Autodesk Fusion 360 part; units mm, degrees
(part 2 of 3)
sketch "Controller support outside regulator reserve (2)" plane through (0, 0, -13) normal (0, 0, 1) x (1, 0, 0) in component "CORE | ElectronicsCassette"
  line L0 (24.2, -4.8) -> (25.8, -4.8)
  line L1 (25.8, -4.8) -> (25.8, -3.2)
  line L2 (25.8, -3.2) -> (24.2, -3.2)
  line L3 (24.2, -3.2) -> (24.2, -4.8)
extrude "Controller support outside regulator reserve (3)" add sketch "Controller support outside regulator reserve (2)" along normal blind 13 bodies 3 in component "CORE | ElectronicsCassette"
ref_plane "WorkPlane17" through (0, 0, -13) normal (0, 0, 1) x (1, 0, 0) in component "CORE | ElectronicsCassette"
sketch "Controller support outside regulator reserve (3)" plane through (0, 0, -13) normal (0, 0, 1) x (1, 0, 0) in component "CORE | ElectronicsCassette"
  line L0 (24.2, 3.2) -> (25.8, 3.2)
  line L1 (25.8, 3.2) -> (25.8, 4.8)
  line L2 (25.8, 4.8) -> (24.2, 4.8)
  line L3 (24.2, 4.8) -> (24.2, 3.2)
extrude "Controller support outside regulator reserve (4)" add sketch "Controller support outside regulator reserve (3)" along normal blind 13 bodies 3 in component "CORE | ElectronicsCassette"
ref_plane "WorkPlane18" through (0, 0, -15) normal (0, 0, 1) x (1, 0, 0) in component "CORE | ElectronicsCassette"
sketch "Reserved harness route at carrier edge" plane through (0, 0, -15) normal (0, 0, 1) x (1, 0, 0) in component "CORE | ElectronicsCassette"
  line L0 (-7, -23.8) -> (7, -23.8)
  arc A0 (7, -26.2) -> (7, -23.8) centre (7, -25) ccw
  line L1 (7, -26.2) -> (-7, -26.2)
  arc A1 (-7, -23.8) -> (-7, -26.2) centre (-7, -25) ccw
  line L2 (-7, 26.2) -> (7, 26.2)
  arc A2 (7, 23.8) -> (7, 26.2) centre (7, 25) ccw
  line L3 (7, 23.8) -> (-7, 23.8)
  arc A3 (-7, 26.2) -> (-7, 23.8) centre (-7, 25) ccw
extrude "Reserved harness route at carrier edge (1)" cut sketch "Reserved harness route at carrier edge" along normal blind 2 bodies 3 in component "CORE | ElectronicsCassette"
ref_plane "WorkPlane1" through (0, 0, 4) normal (0, 0, 1) x (1, 0, 0) in component "LEG | Centred proximal clevis"
sketch "Closed yaw cap" plane through (0, 0, 4) normal (0, 0, 1) x (1, 0, 0) in component "LEG | Centred proximal clevis"
  circle A0 centre (0, 0) radius 16
extrude "Closed yaw cap (1)" add sketch "Closed yaw cap" along normal blind 4.8 separate body makes body 4 in component "LEG | Centred proximal clevis"
ref_plane "WorkPlane2" through (0, 0, 4) normal (0, 0, 1) x (1, 0, 0) in component "LEG | Centred proximal clevis"
sketch "Symmetric short proximal link" plane through (0, 0, 4) normal (0, 0, 1) x (1, 0, 0) in component "LEG | Centred proximal clevis"
  line L0 (0, -16) -> (16, -14)
  line L1 (16, -14) -> (34, -20.8)
  line L2 (34, -20.8) -> (34, 20.8)
  line L3 (34, 20.8) -> (16, 14)
  line L4 (16, 14) -> (0, 16)
  line L5 (0, 16) -> (0, -16)
extrude "Symmetric short proximal link (1)" add sketch "Symmetric short proximal link" along normal blind 2.4 bodies 4 in component "LEG | Centred proximal clevis"
ref_plane "WorkPlane3" through (0, 0, 4) normal (0, 0, 1) x (1, 0, 0) in component "LEG | Centred proximal clevis"
sketch "Yaw output coupling reserve" plane through (0, 0, 4) normal (0, 0, 1) x (1, 0, 0) in component "LEG | Centred proximal clevis"
  circle A0 centre (0, 0) radius 13.8
extrude "Yaw output coupling reserve (1)" cut sketch "Yaw output coupling reserve" along normal blind 3.2 bodies 4 in component "LEG | Centred proximal clevis"
ref_plane "WorkPlane4" through (0, -16.1, 0) normal (0, 1, 0) x (0, 0, 1) in component "LEG | Centred proximal clevis"
sketch "Bilateral internal shoulder support" plane through (0, -16.1, 0) normal (0, 1, 0) x (1, 0, 0) in component "LEG | Centred proximal clevis"
  line L0 (38.0299, -7.6076) -> (49.0299, 9.3924)
  arc A0 (49.0299, 9.3924) -> (40.9701, 14.6076) centre (45, 12) ccw
  line L1 (40.9701, 14.6076) -> (29.9701, -2.3924)
  arc A1 (29.9701, -2.3924) -> (38.0299, -7.6076) centre (34, -5) ccw
extrude "Bilateral internal shoulder support (1)" add sketch "Bilateral internal shoulder support" along normal blind 1.8 bodies 4 in component "LEG | Centred proximal clevis"
ref_plane "WorkPlane5" through (0, -16.1, 0) normal (0, 1, 0) x (0, 0, 1) in component "LEG | Centred proximal clevis"
sketch "Shoulder pivot plate inside upper enclosure" plane through (0, -16.1, 0) normal (0, 1, 0) x (1, 0, 0) in component "LEG | Centred proximal clevis"
  circle A0 centre (45, 12) radius 11.2
extrude "Shoulder pivot plate inside upper enclosure (1)" add sketch "Shoulder pivot plate inside upper enclosure" along normal blind 1.8 bodies 4 in component "LEG | Centred proximal clevis"
ref_plane "WorkPlane6" through (0, -16.1, 0) normal (0, 1, 0) x (0, 0, 1) in component "LEG | Centred proximal clevis"
sketch "Provisional axis/tool access hidden by red upper cover" plane through (0, -16.1, 0) normal (0, 1, 0) x (1, 0, 0) in component "LEG | Centred proximal clevis"
  circle A0 centre (45, 12) radius 3.2
extrude "Provisional axis/tool access hidden by red upper cover (1)" cut sketch "Provisional axis/tool access hidden by red upper cover" along normal blind 1.8 bodies 4 in component "LEG | Centred proximal clevis"
ref_plane "WorkPlane7" through (0, 14.3, 0) normal (0, 1, 0) x (0, 0, 1) in component "LEG | Centred proximal clevis"
sketch "Bilateral internal shoulder support (1)" plane through (0, 14.3, 0) normal (0, 1, 0) x (1, 0, 0) in component "LEG | Centred proximal clevis"
  line L0 (38.0299, -7.6076) -> (49.0299, 9.3924)
  arc A0 (49.0299, 9.3924) -> (40.9701, 14.6076) centre (45, 12) ccw
  line L1 (40.9701, 14.6076) -> (29.9701, -2.3924)
  arc A1 (29.9701, -2.3924) -> (38.0299, -7.6076) centre (34, -5) ccw
extrude "Bilateral internal shoulder support (2)" add sketch "Bilateral internal shoulder support (1)" along normal blind 1.8 bodies 4 in component "LEG | Centred proximal clevis"
ref_plane "WorkPlane8" through (0, 14.3, 0) normal (0, 1, 0) x (0, 0, 1) in component "LEG | Centred proximal clevis"
sketch "Shoulder pivot plate inside upper enclosure (1)" plane through (0, 14.3, 0) normal (0, 1, 0) x (1, 0, 0) in component "LEG | Centred proximal clevis"
  circle A0 centre (45, 12) radius 11.2
extrude "Shoulder pivot plate inside upper enclosure (2)" add sketch "Shoulder pivot plate inside upper enclosure (1)" along normal blind 1.8 bodies 4 in component "LEG | Centred proximal clevis"
ref_plane "WorkPlane9" through (0, 14.3, 0) normal (0, 1, 0) x (0, 0, 1) in component "LEG | Centred proximal clevis"
sketch "Provisional axis/tool access hidden by red upper cover (1)" plane through (0, 14.3, 0) normal (0, 1, 0) x (1, 0, 0) in component "LEG | Centred proximal clevis"
  circle A0 centre (45, 12) radius 3.2
extrude "Provisional axis/tool access hidden by red upper cover (2)" cut sketch "Provisional axis/tool access hidden by red upper cover (1)" along normal blind 1.8 bodies 4 in component "LEG | Centred proximal clevis"
ref_plane "WorkPlane1" through (0, -18.7, 0) normal (0, 1, 0) x (0, 0, 1) in component "LEG | Continuous centred upper enclosure"
sketch "One continuous upper arm outer skin" plane through (0, -18.7, 0) normal (0, 1, 0) x (1, 0, 0) in component "LEG | Continuous centred upper enclosure"
  line L0 (0, -14) -> (52, -14)
  arc A0 (52, -14) -> (52, 14) centre (52, 0) ccw
  line L1 (52, 14) -> (0, 14)
  arc A1 (0, 14) -> (0, -14) centre (0, 0) ccw
extrude "One continuous upper arm outer skin (1)" add sketch "One continuous upper arm outer skin" along normal blind 35.3 separate body makes body 5 in component "LEG | Continuous centred upper enclosure"
ref_plane "WorkPlane2" through (0, -16.9, 0) normal (0, 1, 0) x (0, 0, 1) in component "LEG | Continuous centred upper enclosure"
sketch "Two-actuator interior open at front service cover" plane through (0, -16.9, 0) normal (0, 1, 0) x (1, 0, 0) in component "LEG | Continuous centred upper enclosure"
  line L0 (0, -12.2) -> (52, -12.2)
  arc A0 (52, -12.2) -> (52, 12.2) centre (52, 0) ccw
  line L1 (52, 12.2) -> (0, 12.2)
  arc A1 (0, 12.2) -> (0, -12.2) centre (0, 0) ccw
extrude "Two-actuator interior open at front service cover (1)" cut sketch "Two-actuator interior open at front service cover" along normal blind 33.5 bodies 5 in component "LEG | Continuous centred upper enclosure"
ref_plane "WorkPlane3" through (0, -16.5, 0) normal (0, 1, 0) x (0, 0, 1) in component "LEG | Continuous centred upper enclosure"
sketch "Narrow fixed shoulder clevis entry slot" plane through (0, -16.5, 0) normal (0, 1, 0) x (1, 0, 0) in component "LEG | Continuous centred upper enclosure"
  line L0 (-6, -9) -> (22, -9)
  line L1 (22, -9) -> (22, -26)
  line L2 (22, -26) -> (-6, -26)
  line L3 (-6, -26) -> (-6, -9)
extrude "Narrow fixed shoulder clevis entry slot (1)" cut sketch "Narrow fixed shoulder clevis entry slot" along normal blind 2.5 bodies 5 in component "LEG | Continuous centred upper enclosure"
ref_plane "WorkPlane4" through (0, -16.5, 0) normal (0, 1, 0) x (0, 0, 1) in component "LEG | Continuous centred upper enclosure"
sketch "Narrow lower clevis swept exit slot" plane through (0, -16.5, 0) normal (0, 1, 0) x (1, 0, 0) in component "LEG | Continuous centred upper enclosure"
  line L0 (18, 30) -> (66, 30)
  line L1 (66, 30) -> (66, 7)
  line L2 (66, 7) -> (18, 7)
  line L3 (18, 7) -> (18, 30)
extrude "Narrow lower clevis swept exit slot (1)" cut sketch "Narrow lower clevis swept exit slot" along normal blind 2.5 bodies 5 in component "LEG | Continuous centred upper enclosure"
ref_plane "WorkPlane5" through (0, 14, 0) normal (0, 1, 0) x (0, 0, 1) in component "LEG | Continuous centred upper enclosure"
sketch "Narrow fixed shoulder clevis entry slot (1)" plane through (0, 14, 0) normal (0, 1, 0) x (1, 0, 0) in component "LEG | Continuous centred upper enclosure"
  line L0 (-6, -9) -> (22, -9)
  line L1 (22, -9) -> (22, -26)
  line L2 (22, -26) -> (-6, -26)
  line L3 (-6, -26) -> (-6, -9)
extrude "Narrow fixed shoulder clevis entry slot (2)" cut sketch "Narrow fixed shoulder clevis entry slot (1)" along normal blind 2.5 bodies 5 in component "LEG | Continuous centred upper enclosure"
ref_plane "WorkPlane6" through (0, 14, 0) normal (0, 1, 0) x (0, 0, 1) in component "LEG | Continuous centred upper enclosure"
sketch "Narrow lower clevis swept exit slot (1)" plane through (0, 14, 0) normal (0, 1, 0) x (1, 0, 0) in component "LEG | Continuous centred upper enclosure"
  line L0 (18, 30) -> (66, 30)
  line L1 (66, 30) -> (66, 7)
  line L2 (66, 7) -> (18, 7)
  line L3 (18, 7) -> (18, 30)
extrude "Narrow lower clevis swept exit slot (2)" cut sketch "Narrow lower clevis swept exit slot (1)" along normal blind 2.5 bodies 5 in component "LEG | Continuous centred upper enclosure"
ref_plane "WorkPlane7" through (0, 0, 4) normal (0, 0, 1) x (1, 0, 0) in component "LEG | Continuous centred upper enclosure"
sketch "Upper central retention bridge in actuator gap" plane through (0, 0, 4) normal (0, 0, 1) x (1, 0, 0) in component "LEG | Continuous centred upper enclosure"
  line L0 (22.2, -17.4) -> (29.8, -17.4)
  line L1 (29.8, -17.4) -> (29.8, 16.6)
  line L2 (29.8, 16.6) -> (22.2, 16.6)
  line L3 (22.2, 16.6) -> (22.2, -17.4)
extrude "Upper central retention bridge in actuator gap (1)" add sketch "Upper central retention bridge in actuator gap" along normal blind 8 bodies 5 in component "LEG | Continuous centred upper enclosure"
ref_plane "WorkPlane8" through (0, 0, 4.7) normal (0, 0, 1) x (1, 0, 0) in component "LEG | Continuous centred upper enclosure"
sketch "Keyed cover tongue pocket" plane through (0, 0, 4.7) normal (0, 0, 1) x (1, 0, 0) in component "LEG | Continuous centred upper enclosure"
  line L0 (22.4, 10) -> (29.6, 10)
  line L1 (29.6, 10) -> (29.6, 16.6)
  line L2 (29.6, 16.6) -> (22.4, 16.6)
  line L3 (22.4, 16.6) -> (22.4, 10)
extrude "Keyed cover tongue pocket (1)" cut sketch "Keyed cover tongue pocket" along normal blind 6.8 bodies 5 in component "LEG | Continuous centred upper enclosure"
ref_plane "WorkPlane9" through (0, -18.7, 0) normal (0, 1, 0) x (0, 0, 1) in component "LEG | Continuous centred upper enclosure"
sketch "Single central rear service screw path" plane through (0, -18.7, 0) normal (0, 1, 0) x (1, 0, 0) in component "LEG | Continuous centred upper enclosure"
  circle A0 centre (26, -8.1) radius 1.7
extrude "Single central rear service screw path (1)" cut sketch "Single central rear service screw path" along normal blind 28.9 bodies 5 in component "LEG | Continuous centred upper enclosure"
ref_plane "WorkPlane10" through (0, -18.7, 0) normal (0, 1, 0) x (0, 0, 1) in component "LEG | Continuous centred upper enclosure"
sketch "Flush rear screw head recess" plane through (0, -18.7, 0) normal (0, 1, 0) x (1, 0, 0) in component "LEG | Continuous centred upper enclosure"
  circle A0 centre (26, -8.1) radius 3.1
extrude "Flush rear screw head recess (1)" cut sketch "Flush rear screw head recess" along normal blind 1.8 bodies 5 in component "LEG | Continuous centred upper enclosure"
ref_plane "WorkPlane1" through (0, 16.9, 0) normal (0, 1, 0) x (0, 0, 1) in component "LEG | Full red front service panel"
sketch "Closed front panel hides both actuator bodies" plane through (0, 16.9, 0) normal (0, 1, 0) x (1, 0, 0) in component "LEG | Full red front service panel"
  line L0 (0, -14) -> (52, -14)
  arc A0 (52, -14) -> (52, 14) centre (52, 0) ccw
  line L1 (52, 14) -> (0, 14)
  arc A1 (0, 14) -> (0, -14) centre (0, 0) ccw
extrude "Closed front panel hides both actuator bodies (1)" add sketch "Closed front panel hides both actuator bodies" along normal blind 1.8 separate body makes body 6 in component "LEG | Full red front service panel"
ref_plane "WorkPlane2" through (0, 0, 5) normal (0, 0, 1) x (1, 0, 0) in component "LEG | Full red front service panel"
sketch "Single keyed internal retention tongue" plane through (0, 0, 5) normal (0, 0, 1) x (1, 0, 0) in component "LEG | Full red front service panel"
  line L0 (22.8, 10.2) -> (29.2, 10.2)
  line L1 (29.2, 10.2) -> (29.2, 17)
  line L2 (29.2, 17) -> (22.8, 17)
  line L3 (22.8, 17) -> (22.8, 10.2)
extrude "Single keyed internal retention tongue (1)" add sketch "Single keyed internal retention tongue" along normal blind 6.2 bodies 6 in component "LEG | Full red front service panel"
ref_plane "WorkPlane3" through (0, 10.2, 0) normal (0, 1, 0) x (0, 0, 1) in component "LEG | Full red front service panel"
sketch "Provisional M3 insert cavity" plane through (0, 10.2, 0) normal (0, 1, 0) x (1, 0, 0) in component "LEG | Full red front service panel"
  circle A0 centre (26, -8.1) radius 2.1
extrude "Provisional M3 insert cavity (1)" cut sketch "Provisional M3 insert cavity" along normal blind 4.2 bodies 6 in component "LEG | Full red front service panel"
ref_plane "WorkPlane1" through (0, 14.3, 0) normal (0, 1, 0) x (0, 0, 1) in component "LEG | Centred tapered lower arm"
sketch "Internal forward knee pivot plate" plane through (0, 14.3, 0) normal (0, 1, 0) x (1, 0, 0) in component "LEG | Centred tapered lower arm"
  circle A0 centre (0, 0) radius 11.2
extrude "Internal forward knee pivot plate (1)" add sketch "Internal forward knee pivot plate" along normal blind 1.8 separate body makes body 7 in component "LEG | Centred tapered lower arm"
ref_plane "WorkPlane2" through (0, 14.3, 0) normal (0, 1, 0) x (0, 0, 1) in component "LEG | Centred tapered lower arm"
sketch "Forward inner fork leg" plane through (0, 14.3, 0) normal (0, 1, 0) x (1, 0, 0) in component "LEG | Centred tapered lower arm"
  line L0 (0, 10) -> (14, 9)
  line L1 (14, 9) -> (28, 7.5)
  line L2 (28, 7.5) -> (40, 6.5)
  line L3 (40, 6.5) -> (40, -6.5)
  line L4 (40, -6.5) -> (28, -7.5)
  line L5 (28, -7.5) -> (14, -9)
  line L6 (14, -9) -> (0, -10)
  line L7 (0, -10) -> (0, 10)
extrude "Forward inner fork leg (1)" add sketch "Forward inner fork leg" along normal blind 1.8 bodies 7 in component "LEG | Centred tapered lower arm"
ref_plane "WorkPlane3" through (38, 0, 0) normal (1, 0, 0) x (0, 1, 0) in component "LEG | Centred tapered lower arm"
sketch "Symmetric transition into centred lower beam section" plane through (38, 0, 0) normal (1, 0, 0) x (0, 0, -1) in component "LEG | Centred tapered lower arm"
  line L0 (6.5, -14.9) -> (6.5, 14.9)
  arc A0 (6.5, 14.9) -> (5.3, 16.1) centre (5.3, 14.9) ccw
  line L1 (5.3, 16.1) -> (-5.3, 16.1)
  arc A1 (-5.3, 16.1) -> (-6.5, 14.9) centre (-5.3, 14.9) ccw
  line L2 (-6.5, 14.9) -> (-6.5, -14.9)
  arc A2 (-6.5, -14.9) -> (-5.3, -16.1) centre (-5.3, -14.9) ccw
  line L3 (-5.3, -16.1) -> (5.3, -16.1)
  arc A3 (5.3, -16.1) -> (6.5, -14.9) centre (5.3, -14.9) ccw
ref_plane "WorkPlane4" through (48, 0, 0) normal (1, 0, 0) x (0, 1, 0) in component "LEG | Centred tapered lower arm"
sketch "Symmetric transition into centred lower beam section (1)" plane through (48, 0, 0) normal (1, 0, 0) x (0, 0, -1) in component "LEG | Centred tapered lower arm"
  line L0 (5.5, -2.8) -> (5.5, 2.8)
  arc A0 (5.5, 2.8) -> (4.3, 4) centre (4.3, 2.8) ccw
  line L1 (4.3, 4) -> (-4.3, 4)
  arc A1 (-4.3, 4) -> (-5.5, 2.8) centre (-4.3, 2.8) ccw
  line L2 (-5.5, 2.8) -> (-5.5, -2.8)
  arc A2 (-5.5, -2.8) -> (-4.3, -4) centre (-4.3, -2.8) ccw
  line L3 (-4.3, -4) -> (4.3, -4)
  arc A3 (4.3, -4) -> (5.5, -2.8) centre (4.3, -2.8) ccw
loft "Symmetric transition into centred lower beam" add profiles "Symmetric transition into centred lower beam section", "Symmetric transition into centred lower beam section (1)" section 1 section 2 bodies 7 in component "LEG | Centred tapered lower arm"
ref_plane "WorkPlane5" through (0, -16.1, 0) normal (0, 1, 0) x (0, 0, 1) in component "LEG | Centred tapered lower arm"
sketch "Rear inner fork leg linked by transition" plane through (0, -16.1, 0) normal (0, 1, 0) x (1, 0, 0) in component "LEG | Centred tapered lower arm"
  line L0 (0, 10) -> (14, 9)
  line L1 (14, 9) -> (28, 7.5)
  line L2 (28, 7.5) -> (40, 6.5)
  line L3 (40, 6.5) -> (40, -6.5)
  line L4 (40, -6.5) -> (28, -7.5)
  line L5 (28, -7.5) -> (14, -9)
  line L6 (14, -9) -> (0, -10)
  line L7 (0, -10) -> (0, 10)
extrude "Rear inner fork leg linked by transition (1)" add sketch "Rear inner fork leg linked by transition" along normal blind 1.8 bodies 7 in component "LEG | Centred tapered lower arm"
ref_plane "WorkPlane6" through (0, -16.1, 0) normal (0, 1, 0) x (0, 0, 1) in component "LEG | Centred tapered lower arm"
sketch "Internal rear knee pivot plate" plane through (0, -16.1, 0) normal (0, 1, 0) x (1, 0, 0) in component "LEG | Centred tapered lower arm"
  circle A0 centre (0, 0) radius 11.2
extrude "Internal rear knee pivot plate (1)" add sketch "Internal rear knee pivot plate" along normal blind 1.8 bodies 7 in component "LEG | Centred tapered lower arm"
ref_plane "WorkPlane7" through (48, 0, 0) normal (1, 0, 0) x (0, 1, 0) in component "LEG | Centred tapered lower arm"
sketch "Slim continuous tapered centred beam section" plane through (48, 0, 0) normal (1, 0, 0) x (0, 0, -1) in component "LEG | Centred tapered lower arm"
  line L0 (5.5, -2.8) -> (5.5, 2.8)
  arc A0 (5.5, 2.8) -> (4.3, 4) centre (4.3, 2.8) ccw
  line L1 (4.3, 4) -> (-4.3, 4)
  arc A1 (-4.3, 4) -> (-5.5, 2.8) centre (-4.3, 2.8) ccw
  line L2 (-5.5, 2.8) -> (-5.5, -2.8)
  arc A2 (-5.5, -2.8) -> (-4.3, -4) centre (-4.3, -2.8) ccw
  line L3 (-4.3, -4) -> (4.3, -4)
  arc A3 (4.3, -4) -> (5.5, -2.8) centre (4.3, -2.8) ccw
ref_plane "WorkPlane8" through (93, 0, 0) normal (1, 0, 0) x (0, 1, 0) in component "LEG | Centred tapered lower arm"
sketch "Slim continuous tapered centred beam section (1)" plane through (93, 0, 0) normal (1, 0, 0) x (0, 0, -1) in component "LEG | Centred tapered lower arm"
  line L0 (2.3, -2.4) -> (2.3, 2.4)
  arc A0 (2.3, 2.4) -> (1.3, 3.4) centre (1.3, 2.4) ccw
  line L1 (1.3, 3.4) -> (-1.3, 3.4)
  arc A1 (-1.3, 3.4) -> (-2.3, 2.4) centre (-1.3, 2.4) ccw
  line L2 (-2.3, 2.4) -> (-2.3, -2.4)
  arc A2 (-2.3, -2.4) -> (-1.3, -3.4) centre (-1.3, -2.4) ccw
  line L3 (-1.3, -3.4) -> (1.3, -3.4)
  arc A3 (1.3, -3.4) -> (2.3, -2.4) centre (1.3, -2.4) ccw
loft "Slim continuous tapered centred beam" add profiles "Slim continuous tapered centred beam section", "Slim continuous tapered centred beam section (1)" section 1 section 2 bodies 7 in component "LEG | Centred tapered lower arm"
ref_plane "WorkPlane9" through (0, -16.1, 0) normal (0, 1, 0) x (0, 0, 1) in component "LEG | Centred tapered lower arm"
sketch "Knee axis/tool access concealed by upper service panel" plane through (0, -16.1, 0) normal (0, 1, 0) x (1, 0, 0) in component "LEG | Centred tapered lower arm"
  circle A0 centre (0, 0) radius 3.2
extrude "Knee axis/tool access concealed by upper service panel (1)" cut sketch "Knee axis/tool access concealed by upper service panel" along normal blind 1.8 bodies 7 in component "LEG | Centred tapered lower arm"
ref_plane "WorkPlane10" through (0, 14.3, 0) normal (0, 1, 0) x (0, 0, 1) in component "LEG | Centred tapered lower arm"
sketch "Knee axis/tool access concealed by upper service panel (1)" plane through (0, 14.3, 0) normal (0, 1, 0) x (1, 0, 0) in component "LEG | Centred tapered lower arm"
  circle A0 centre (0, 0) radius 3.2
extrude "Knee axis/tool access concealed by upper service panel (2)" cut sketch "Knee axis/tool access concealed by upper service panel (1)" along normal blind 1.8 bodies 7 in component "LEG | Centred tapered lower arm"
ref_plane "WorkPlane1" through (0, -5.5, 0) normal (0, 1, 0) x (0, 0, 1) in component "FOOT | Centred soft toe boot"
sketch "Symmetric compliant toe" plane through (0, -5.5, 0) normal (0, 1, 0) x (1, 0, 0) in component "FOOT | Centred soft toe boot"
  circle A0 centre (93, 0) radius 5.5
extrude "Symmetric compliant toe (1)" add sketch "Symmetric compliant toe" along normal blind 11 separate body makes body 8 in component "FOOT | Centred soft toe boot"
ref_plane "WorkPlane2" through (0, -4.6, 0) normal (0, 1, 0) x (0, 0, 1) in component "FOOT | Centred soft toe boot"
sketch "Centred toe socket with clearance; retention TBD" plane through (0, -4.6, 0) normal (0, 1, 0) x (1, 0, 0) in component "FOOT | Centred soft toe boot"
  line L0 (87.8, 3.2) -> (93.5, 3.2)
  arc A0 (94.3, 2.4) -> (93.5, 3.2) centre (93.5, 2.4) ccw
  line L1 (94.3, 2.4) -> (94.3, -2.4)
  arc A1 (93.5, -3.2) -> (94.3, -2.4) centre (93.5, -2.4) ccw
  line L2 (93.5, -3.2) -> (87.8, -3.2)
  arc A2 (87, -2.4) -> (87.8, -3.2) centre (87.8, -2.4) ccw
  line L3 (87, -2.4) -> (87, 2.4)
  arc A3 (87.8, 3.2) -> (87, 2.4) centre (87.8, 2.4) ccw
extrude "Centred toe socket with clearance; retention TBD (1)" cut sketch "Centred toe socket with clearance; retention TBD" along normal blind 9.2 bodies 8 in component "FOOT | Centred soft toe boot"
ref_plane "WorkPlane1" through (0, 0, -28) normal (0, 0, 1) x (1, 0, 0) in component "KEEP-OUT | YawReserve · actuator not selected"
sketch "Nominal actuator case only" plane through (0, 0, -28) normal (0, 0, 1) x (1, 0, 0) in component "KEEP-OUT | YawReserve · actuator not selected"
  line L0 (-22, -6.5) -> (10, -6.5)
  line L1 (10, -6.5) -> (10, 6.5)
  line L2 (10, 6.5) -> (-22, 6.5)
  line L3 (-22, 6.5) -> (-22, -6.5)
extrude "Nominal actuator case only (1)" add sketch "Nominal actuator case only" along normal blind 27 separate body makes body 9 in component "KEEP-OUT | YawReserve · actuator not selected"
ref_plane "WorkPlane1" through (0, 0, -6.5) normal (0, 0, 1) x (1, 0, 0) in component "KEEP-OUT | HipReserve · actuator not selected"
sketch "Nominal actuator case only (2)" plane through (0, 0, -6.5) normal (0, 0, 1) x (1, 0, 0) in component "KEEP-OUT | HipReserve · actuator not selected"
  line L0 (-10, -13.5) -> (22, -13.5)
  line L1 (22, -13.5) -> (22, 13.5)
  line L2 (22, 13.5) -> (-10, 13.5)
  line L3 (-10, 13.5) -> (-10, -13.5)
extrude "Nominal actuator case only (1)'" add sketch "Nominal actuator case only (2)" along normal blind 13 separate body makes body 10 in component "KEEP-OUT | HipReserve · actuator not selected"
ref_plane "WorkPlane1" through (0, 0, -6.5) normal (0, 0, 1) x (1, 0, 0) in component "KEEP-OUT | KneeReserve · actuator not selected"
sketch "Nominal actuator case only (3)" plane through (0, 0, -6.5) normal (0, 0, 1) x (1, 0, 0) in component "KEEP-OUT | KneeReserve · actuator not selected"
  line L0 (30, -13.5) -> (62, -13.5)
  line L1 (62, -13.5) -> (62, 13.5)
  line L2 (62, 13.5) -> (30, 13.5)
  line L3 (30, 13.5) -> (30, -13.5)
extrude "Nominal actuator case only (1)''" add sketch "Nominal actuator case only (3)" along normal blind 13 separate body makes body 11 in component "KEEP-OUT | KneeReserve · actuator not selected"
sketch "Sketch1" plane through (0, 0, 0) normal (0, 0, 1) x (1, 0, 0)
  point P0 (49, 0)
  point P1 (59, 0)
  point P2 (49, 10)
ref_plane "WorkPlane1" through (49, 0, 0) normal (0, 0, 1) x (1, 0, 0)
sketch "Sketch2" plane through (0, 0, 0) normal (0, 0, 1) x (1, 0, 0)
  circle A0 centre (49, 0) radius 1
sketch "Sketch3" plane through (0, 0, 0) normal (0, 0, 1) x (1, 0, 0)
  point P0 (94, 0)
  point P1 (94, 0)
  point P2 (104, 0)
ref_plane "WorkPlane2" through (94, 0, -12) normal (0, 1, 0) x (-1, 0, 0)
sketch "Sketch4" plane through (0, 0, 0) normal (0, 1, 0) x (1, 0, 0)
  circle A0 centre (94, 12) radius 1
sketch "Sketch5" plane through (0, 0, 0) normal (0, 0, 1) x (1, 0, 0)
  point P0 (123.826, 0)
  point P1 (123.826, 0)
  point P2 (133.826, 0)
ref_plane "WorkPlane3" through (123.826, 0, 30.5959) normal (0, 1, 0) x (-1, 0, 0)
sketch "Sketch6" plane through (0, 0, 0) normal (0, 1, 0) x (1, 0, 0)
  circle A0 centre (123.826, -30.5959) radius 1
sketch "Sketch7" plane through (0, 0, 0) normal (0, 0, 1) x (1, 0, 0)
  point P0 (24.5, 42.4352)
  point P1 (34.5, 42.4352)
  point P2 (24.5, 52.4352)
ref_plane "WorkPlane4" through (24.5, 42.4352, 0) normal (0, 0, 1) x (1, 0, 0)
sketch "Sketch8" plane through (0, 0, 0) normal (0, 0, 1) x (1, 0, 0)
  circle A0 centre (24.5, 42.4352) radius 1
sketch "Sketch9" plane through (0, 0, 0) normal (0, 0, 1) x (1, 0, 0)
  point P0 (47, 81.4064)
  point P1 (47, 81.4064)
  point P2 (52, 90.0666)
ref_plane "WorkPlane5" through (47, 81.4064, -12) normal (-0.866025, 0.5, 0) x (-0.5, -0.866025, 0)
sketch "Sketch10" plane through (0, 0, 0) normal (-0.866025, 0.5, 0) x (-0.5, -0.866025, 0)
  circle A0 centre (-94, -12) radius 1
sketch "Sketch11" plane through (0, 0, 0) normal (0, 0, 1) x (1, 0, 0)
  point P0 (61.913, 107.2364)
  point P1 (61.913, 107.2364)
  point P2 (66.913, 115.8967)
ref_plane "WorkPlane6" through (61.913, 107.2364, 30.5959) normal (-0.866025, 0.5, 0) x (-0.5, -0.866025, 0)
sketch "Sketch12" plane through (0, 0, 0) normal (-0.866025, 0.5, 0) x (-0.5, -0.866025, 0)
  circle A0 centre (-123.826, 30.5959) radius 1
sketch "Sketch13" plane through (0, 0, 0) normal (0, 0, 1) x (1, 0, 0)
  point P0 (-24.5, 42.4352)
  point P1 (-14.5, 42.4352)
  point P2 (-24.5, 52.4352)
ref_plane "WorkPlane7" through (-24.5, 42.4352, 0) normal (0, 0, 1) x (1, 0, 0)
sketch "Sketch14" plane through (0, 0, 0) normal (0, 0, 1) x (1, 0, 0)
  circle A0 centre (-24.5, 42.4352) radius 1
sketch "Sketch15" plane through (0, 0, 0) normal (0, 0, 1) x (1, 0, 0)
  point P0 (-47, 81.4064)
  point P1 (-47, 81.4064)
  point P2 (-52, 90.0666)
ref_plane "WorkPlane8" through (-47, 81.4064, -12) normal (-0.866025, -0.5, 0) x (0.5, -0.866025, 0)
sketch "Sketch16" plane through (0, 0, 0) normal (-0.866025, -0.5, 0) x (0.5, -0.866025, 0)
  circle A0 centre (-94, -12) radius 1
sketch "Sketch17" plane through (0, 0, 0) normal (0, 0, 1) x (1, 0, 0)
  point P0 (-61.913, 107.2364)
  point P1 (-61.913, 107.2364)
  point P2 (-66.913, 115.8967)
ref_plane "WorkPlane9" through (-61.913, 107.2364, 30.5959) normal (-0.866025, -0.5, 0) x (0.5, -0.866025, 0)
sketch "Sketch18" plane through (0, 0, 0) normal (-0.866025, -0.5, 0) x (0.5, -0.866025, 0)
  circle A0 centre (-123.826, 30.5959) radius 1
sketch "Sketch19" plane through (0, 0, 0) normal (0, 0, 1) x (1, 0, 0)
  point P0 (-49, 0)
  point P1 (-39, 0)
  point P2 (-49, 10)
ref_plane "WorkPlane10" through (-49, 0, 0) normal (0, 0, 1) x (1, 0, 0)
sketch "Sketch20" plane through (0, 0, 0) normal (0, 0, 1) x (1, 0, 0)
  circle A0 centre (-49, 0) radius 1
sketch "Sketch21" plane through (0, 0, 0) normal (0, 0, 1) x (1, 0, 0)
  point P0 (-94, 0)
  point P1 (-94, 0)
  point P2 (-104, 0)
ref_plane "WorkPlane11" through (-94, 0, -12) normal (0, -1, 0) x (1, 0, 0)
sketch "Sketch22" plane through (0, 0, 0) normal (0, -1, 0) x (-1, 0, 0)
  circle A0 centre (94, 12) radius 1
sketch "Sketch23" plane through (0, 0, 0) normal (0, 0, 1) x (1, 0, 0)
  point P0 (-123.826, 0)
  point P1 (-123.826, 0)
  point P2 (-133.826, 0)
ref_plane "WorkPlane12" through (-123.826, 0, 30.5959) normal (0, -1, 0) x (1, 0, 0)
sketch "Sketch24" plane through (0, 0, 0) normal (0, -1, 0) x (-1, 0, 0)
  circle A0 centre (123.826, -30.5959) radius 1
sketch "Sketch25" plane through (0, 0, 0) normal (0, 0, 1) x (1, 0, 0)
  point P0 (-24.5, -42.4352)
  point P1 (-14.5, -42.4352)
  point P2 (-24.5, -32.4352)
ref_plane "WorkPlane13" through (-24.5, -42.4352, 0) normal (0, 0, 1) x (1, 0, 0)
sketch "Sketch26" plane through (0, 0, 0) normal (0, 0, 1) x (1, 0, 0)
  circle A0 centre (-24.5, -42.4352) radius 1
sketch "Sketch27" plane through (0, 0, 0) normal (0, 0, 1) x (1, 0, 0)
  point P0 (-47, -81.4064)
  point P1 (-47, -81.4064)
  point P2 (-52, -90.0666)
ref_plane "WorkPlane14" through (-47, -81.4064, -12) normal (0.866025, -0.5, 0) x (0.5, 0.866025, 0)
sketch "Sketch28" plane through (0, 0, 0) normal (0.866025, -0.5, 0) x (0.5, 0.866025, 0)
  circle A0 centre (-94, -12) radius 1
sketch "Sketch29" plane through (0, 0, 0) normal (0, 0, 1) x (1, 0, 0)
  point P0 (-61.913, -107.2364)
  point P1 (-61.913, -107.2364)
  point P2 (-66.913, -115.8967)
ref_plane "WorkPlane15" through (-61.913, -107.2364, 30.5959) normal (0.866025, -0.5, 0) x (0.5, 0.866025, 0)
sketch "Sketch30" plane through (0, 0, 0) normal (0.866025, -0.5, 0) x (0.5, 0.866025, 0)
  circle A0 centre (-123.826, 30.5959) radius 1
sketch "Sketch31" plane through (0, 0, 0) normal (0, 0, 1) x (1, 0, 0)
  point P0 (24.5, -42.4352)
  point P1 (34.5, -42.4352)
  point P2 (24.5, -32.4352)
ref_plane "WorkPlane16" through (24.5, -42.4352, 0) normal (0, 0, 1) x (1, 0, 0)
sketch "Sketch32" plane through (0, 0, 0) normal (0, 0, 1) x (1, 0, 0)
  circle A0 centre (24.5, -42.4352) radius 1
sketch "Sketch33" plane through (0, 0, 0) normal (0, 0, 1) x (1, 0, 0)
  point P0 (47, -81.4064)
  point P1 (47, -81.4064)
  point P2 (52, -90.0666)
ref_plane "WorkPlane17" through (47, -81.4064, -12) normal (0.866025, 0.5, 0) x (-0.5, 0.866025, 0)
sketch "Sketch34" plane through (0, 0, 0) normal (0.866025, 0.5, 0) x (-0.5, 0.866025, 0)
  circle A0 centre (-94, -12) radius 1
sketch "Sketch35" plane through (0, 0, 0) normal (0, 0, 1) x (1, 0, 0)
  point P0 (61.913, -107.2364)
  point P1 (61.913, -107.2364)
  point P2 (66.913, -115.8967)
ref_plane "WorkPlane18" through (61.913, -107.2364, 30.5959) normal (0.866025, 0.5, 0) x (-0.5, 0.866025, 0)
sketch "Sketch36" plane through (0, 0, 0) normal (0.866025, 0.5, 0) x (-0.5, 0.866025, 0)
  circle A0 centre (-123.826, 30.5959) radius 1
ref_plane "WorkPlane1" through (0, 0, -29) normal (0, 0, 1) x (1, 0, 0) in component "CORE | BatteryReserve"
sketch "Reserved component keep-out envelope" plane through (0, 0, -29) normal (0, 0, 1) x (1, 0, 0) in component "CORE | BatteryReserve"
  line L0 (-21.5, -11.5) -> (21.5, -11.5)
  line L1 (21.5, -11.5) -> (21.5, 11.5)
  line L2 (21.5, 11.5) -> (-21.5, 11.5)
  line L3 (-21.5, 11.5) -> (-21.5, -11.5)
extrude "Reserved component keep-out envelope (1)" add sketch "Reserved component keep-out envelope" along normal blind 13 separate body makes body 12 in component "CORE | BatteryReserve"
ref_plane "WorkPlane1" through (0, 0, -12) normal (0, 0, 1) x (1, 0, 0) in component "CORE | RegulatorReserve"
sketch "Reserved component keep-out envelope (2)" plane through (0, 0, -12) normal (0, 0, 1) x (1, 0, 0) in component "CORE | RegulatorReserve"
  line L0 (-17, -22) -> (17, -22)
  line L1 (17, -22) -> (17, 22)
  line L2 (17, 22) -> (-17, 22)
  line L3 (-17, 22) -> (-17, -22)
extrude "Reserved component keep-out envelope (1)'" add sketch "Reserved component keep-out envelope (2)" along normal blind 10 separate body makes body 13 in component "CORE | RegulatorReserve"
sketch "Reserved component keep-out envelope (3)" plane through (0, 0, 0) normal (0, 0, 1) x (1, 0, 0) in component "CORE | ESP32Reserve"
  line L0 (-26, -12) -> (26, -12)
  line L1 (26, -12) -> (26, 12)
  line L2 (26, 12) -> (-26, 12)
  line L3 (-26, 12) -> (-26, -12)
extrude "Reserved component keep-out envelope (1)''" add sketch "Reserved component keep-out envelope (3)" along normal blind 8 separate body makes body 14 in component "CORE | ESP32Reserve"
ref_plane "WorkPlane1" through (0, 0, -30) normal (0, 0, 1) x (1, 0, 0) in component "SERVICE HARDWARE | Core lid 1"
sketch "M3 shaft envelope; threads not modeled" plane through (0, 0, -30) normal (0, 0, 1) x (1, 0, 0) in component "SERVICE HARDWARE | Core lid 1"
  circle A0 centre (51.9615, 30) radius 1.5
extrude "M3 shaft envelope; threads not modeled (1)" add sketch "M3 shaft envelope; threads not modeled" along normal blind 30 separate body makes body 15 in component "SERVICE HARDWARE | Core lid 1"
ref_plane "WorkPlane2" through (0, 0, -31.8) normal (0, 0, 1) x (1, 0, 0) in component "SERVICE HARDWARE | Core lid 1"
sketch "Recessed socket head" plane through (0, 0, -31.8) normal (0, 0, 1) x (1, 0, 0) in component "SERVICE HARDWARE | Core lid 1"
  circle A0 centre (51.9615, 30) radius 2.8
extrude "Recessed socket head (1)" add sketch "Recessed socket head" along normal blind 1.8 bodies 15 in component "SERVICE HARDWARE | Core lid 1"
ref_plane "WorkPlane1" through (0, 0, -30) normal (0, 0, 1) x (1, 0, 0) in component "SERVICE HARDWARE | Core lid 2"
sketch "M3 shaft envelope; threads not modeled (2)" plane through (0, 0, -30) normal (0, 0, 1) x (1, 0, 0) in component "SERVICE HARDWARE | Core lid 2"
  circle A0 centre (-51.9615, 30) radius 1.5
extrude "M3 shaft envelope; threads not modeled (1)'" add sketch "M3 shaft envelope; threads not modeled (2)" along normal blind 30 separate body makes body 16 in component "SERVICE HARDWARE | Core lid 2"
ref_plane "WorkPlane2" through (0, 0, -31.8) normal (0, 0, 1) x (1, 0, 0) in component "SERVICE HARDWARE | Core lid 2"
sketch "Recessed socket head (2)" plane through (0, 0, -31.8) normal (0, 0, 1) x (1, 0, 0) in component "SERVICE HARDWARE | Core lid 2"
  circle A0 centre (-51.9615, 30) radius 2.8
extrude "Recessed socket head (1)'" add sketch "Recessed socket head (2)" along normal blind 1.8 bodies 16 in component "SERVICE HARDWARE | Core lid 2"
ref_plane "WorkPlane1" through (0, 0, -30) normal (0, 0, 1) x (1, 0, 0) in component "SERVICE HARDWARE | Core lid 3"
sketch "M3 shaft envelope; threads not modeled (3)" plane through (0, 0, -30) normal (0, 0, 1) x (1, 0, 0) in component "SERVICE HARDWARE | Core lid 3"
  circle A0 centre (-51.9615, -30) radius 1.5
extrude "M3 shaft envelope; threads not modeled (1)''" add sketch "M3 shaft envelope; threads not modeled (3)" along normal blind 30 separate body makes body 17 in component "SERVICE HARDWARE | Core lid 3"
ref_plane "WorkPlane2" through (0, 0, -31.8) normal (0, 0, 1) x (1, 0, 0) in component "SERVICE HARDWARE | Core lid 3"
sketch "Recessed socket head (3)" plane through (0, 0, -31.8) normal (0, 0, 1) x (1, 0, 0) in component "SERVICE HARDWARE | Core lid 3"
  circle A0 centre (-51.9615, -30) radius 2.8
extrude "Recessed socket head (1)''" add sketch "Recessed socket head (3)" along normal blind 1.8 bodies 17 in component "SERVICE HARDWARE | Core lid 3"
ref_plane "WorkPlane1" through (0, 0, -30) normal (0, 0, 1) x (1, 0, 0) in component "SERVICE HARDWARE | Core lid 4"
sketch "M3 shaft envelope; threads not modeled (4)" plane through (0, 0, -30) normal (0, 0, 1) x (1, 0, 0) in component "SERVICE HARDWARE | Core lid 4"
  circle A0 centre (51.9615, -30) radius 1.5
extrude "M3 shaft envelope; threads not modeled (1)'''" add sketch "M3 shaft envelope; threads not modeled (4)" along normal blind 30 separate body makes body 18 in component "SERVICE HARDWARE | Core lid 4"
ref_plane "WorkPlane2" through (0, 0, -31.8) normal (0, 0, 1) x (1, 0, 0) in component "SERVICE HARDWARE | Core lid 4"
sketch "Recessed socket head (4)" plane through (0, 0, -31.8) normal (0, 0, 1) x (1, 0, 0) in component "SERVICE HARDWARE | Core lid 4"
  circle A0 centre (51.9615, -30) radius 2.8
extrude "Recessed socket head (1)'''" add sketch "Recessed socket head (4)" along normal blind 1.8 bodies 18 in component "SERVICE HARDWARE | Core lid 4"
ref_plane "WorkPlane1" through (0, 0, -19) normal (0, 0, 1) x (1, 0, 0) in component "SERVICE HARDWARE | Cassette 1"
sketch "M3 shaft envelope; threads not modeled (5)" plane through (0, 0, -19) normal (0, 0, 1) x (1, 0, 0) in component "SERVICE HARDWARE | Cassette 1"
  circle A0 centre (21, 16) radius 1.5
extrude "M3 shaft envelope; threads not modeled (1)''''" add sketch "M3 shaft envelope; threads not modeled (5)" along normal blind 6 separate body makes body 19 in component "SERVICE HARDWARE | Cassette 1"
ref_plane "WorkPlane2" through (0, 0, -13) normal (0, 0, 1) x (1, 0, 0) in component "SERVICE HARDWARE | Cassette 1"
sketch "Recessed socket head (5)" plane through (0, 0, -13) normal (0, 0, 1) x (1, 0, 0) in component "SERVICE HARDWARE | Cassette 1"
  circle A0 centre (21, 16) radius 2.8
extrude "Recessed socket head (1)''''" add sketch "Recessed socket head (5)" along normal blind 1.8 bodies 19 in component "SERVICE HARDWARE | Cassette 1"
ref_plane "WorkPlane1" through (0, 0, -19) normal (0, 0, 1) x (1, 0, 0) in component "SERVICE HARDWARE | Cassette 2"
sketch "M3 shaft envelope; threads not modeled (6)" plane through (0, 0, -19) normal (0, 0, 1) x (1, 0, 0) in component "SERVICE HARDWARE | Cassette 2"
  circle A0 centre (-21, -16) radius 1.5
extrude "M3 shaft envelope; threads not modeled (1)'''''" add sketch "M3 shaft envelope; threads not modeled (6)" along normal blind 6 separate body makes body 20 in component "SERVICE HARDWARE | Cassette 2"
ref_plane "WorkPlane2" through (0, 0, -13) normal (0, 0, 1) x (1, 0, 0) in component "SERVICE HARDWARE | Cassette 2"
sketch "Recessed socket head (6)" plane through (0, 0, -13) normal (0, 0, 1) x (1, 0, 0) in component "SERVICE HARDWARE | Cassette 2"
  circle A0 centre (-21, -16) radius 2.8
extrude "Recessed socket head (1)'''''" add sketch "Recessed socket head (6)" along normal blind 1.8 bodies 20 in component "SERVICE HARDWARE | Cassette 2"
ref_plane "WorkPlane1" through (0, -16.9, 0) normal (0, 1, 0) x (0, 0, 1) in component "SERVICE HARDWARE | L1 upper cover"
sketch "M3 shaft envelope; threads not modeled (7)" plane through (0, -16.9, 0) normal (0, 1, 0) x (1, 0, 0) in component "SERVICE HARDWARE | L1 upper cover"
  circle A0 centre (26, -8.1) radius 1.5
extrude "M3 shaft envelope; threads not modeled (1)''''''" add sketch "M3 shaft envelope; threads not modeled (7)" along normal blind 30 separate body makes body 21 in component "SERVICE HARDWARE | L1 upper cover"
ref_plane "WorkPlane2" through (0, -18.7, 0) normal (0, 1, 0) x (0, 0, 1) in component "SERVICE HARDWARE | L1 upper cover"
sketch "Recessed socket head (7)" plane through (0, -18.7, 0) normal (0, 1, 0) x (1, 0, 0) in component "SERVICE HARDWARE | L1 upper cover"
  circle A0 centre (26, -8.1) radius 2.8
extrude "Recessed socket head (1)''''''" add sketch "Recessed socket head (7)" along normal blind 1.8 bodies 21 in component "SERVICE HARDWARE | L1 upper cover"
ref_plane "WorkPlane1" through (0, -16.9, 0) normal (0, 1, 0) x (0, 0, 1) in component "SERVICE HARDWARE | L2 upper cover"
sketch "M3 shaft envelope; threads not modeled (8)" plane through (0, -16.9, 0) normal (0, 1, 0) x (1, 0, 0) in component "SERVICE HARDWARE | L2 upper cover"
  circle A0 centre (26, -8.1) radius 1.5
extrude "M3 shaft envelope; threads not modeled (1)'''''''" add sketch "M3 shaft envelope; threads not modeled (8)" along normal blind 30 separate body makes body 22 in component "SERVICE HARDWARE | L2 upper cover"
ref_plane "WorkPlane2" through (0, -18.7, 0) normal (0, 1, 0) x (0, 0, 1) in component "SERVICE HARDWARE | L2 upper cover"
sketch "Recessed socket head (8)" plane through (0, -18.7, 0) normal (0, 1, 0) x (1, 0, 0) in component "SERVICE HARDWARE | L2 upper cover"
  circle A0 centre (26, -8.1) radius 2.8
extrude "Recessed socket head (1)'''''''" add sketch "Recessed socket head (8)" along normal blind 1.8 bodies 22 in component "SERVICE HARDWARE | L2 upper cover"
ref_plane "WorkPlane1" through (0, -16.9, 0) normal (0, 1, 0) x (0, 0, 1) in component "SERVICE HARDWARE | L3 upper cover"
sketch "M3 shaft envelope; threads not modeled (9)" plane through (0, -16.9, 0) normal (0, 1, 0) x (1, 0, 0) in component "SERVICE HARDWARE | L3 upper cover"
  circle A0 centre (26, -8.1) radius 1.5
extrude "M3 shaft envelope; threads not modeled (1)''''''''" add sketch "M3 shaft envelope; threads not modeled (9)" along normal blind 30 separate body makes body 23 in component "SERVICE HARDWARE | L3 upper cover"
ref_plane "WorkPlane2" through (0, -18.7, 0) normal (0, 1, 0) x (0, 0, 1) in component "SERVICE HARDWARE | L3 upper cover"
sketch "Recessed socket head (9)" plane through (0, -18.7, 0) normal (0, 1, 0) x (1, 0, 0) in component "SERVICE HARDWARE | L3 upper cover"
  circle A0 centre (26, -8.1) radius 2.8
extrude "Recessed socket head (1)''''''''" add sketch "Recessed socket head (9)" along normal blind 1.8 bodies 23 in component "SERVICE HARDWARE | L3 upper cover"
ref_plane "WorkPlane1" through (0, -16.9, 0) normal (0, 1, 0) x (0, 0, 1) in component "SERVICE HARDWARE | L4 upper cover"
sketch "M3 shaft envelope; threads not modeled (10)" plane through (0, -16.9, 0) normal (0, 1, 0) x (1, 0, 0) in component "SERVICE HARDWARE | L4 upper cover"
  circle A0 centre (26, -8.1) radius 1.5
extrude "M3 shaft envelope; threads not modeled (1)'''''''''" add sketch "M3 shaft envelope; threads not modeled (10)" along normal blind 30 separate body makes body 24 in component "SERVICE HARDWARE | L4 upper cover"
ref_plane "WorkPlane2" through (0, -18.7, 0) normal (0, 1, 0) x (0, 0, 1) in component "SERVICE HARDWARE | L4 upper cover"
sketch "Recessed socket head (10)" plane through (0, -18.7, 0) normal (0, 1, 0) x (1, 0, 0) in component "SERVICE HARDWARE | L4 upper cover"
  circle A0 centre (26, -8.1) radius 2.8
extrude "Recessed socket head (1)'''''''''" add sketch "Recessed socket head (10)" along normal blind 1.8 bodies 24 in component "SERVICE HARDWARE | L4 upper cover"
ref_plane "WorkPlane1" through (0, -16.9, 0) normal (0, 1, 0) x (0, 0, 1) in component "SERVICE HARDWARE | L5 upper cover"
sketch "M3 shaft envelope; threads not modeled (11)" plane through (0, -16.9, 0) normal (0, 1, 0) x (1, 0, 0) in component "SERVICE HARDWARE | L5 upper cover"
  circle A0 centre (26, -8.1) radius 1.5
extrude "M3 shaft envelope; threads not modeled (1)''''''''''" add sketch "M3 shaft envelope; threads not modeled (11)" along normal blind 30 separate body makes body 25 in component "SERVICE HARDWARE | L5 upper cover"
ref_plane "WorkPlane2" through (0, -18.7, 0) normal (0, 1, 0) x (0, 0, 1) in component "SERVICE HARDWARE | L5 upper cover"
sketch "Recessed socket head (11)" plane through (0, -18.7, 0) normal (0, 1, 0) x (1, 0, 0) in component "SERVICE HARDWARE | L5 upper cover"
  circle A0 centre (26, -8.1) radius 2.8
extrude "Recessed socket head (1)''''''''''" add sketch "Recessed socket head (11)" along normal blind 1.8 bodies 25 in component "SERVICE HARDWARE | L5 upper cover"
ref_plane "WorkPlane1" through (0, -16.9, 0) normal (0, 1, 0) x (0, 0, 1) in component "SERVICE HARDWARE | L6 upper cover"
sketch "M3 shaft envelope; threads not modeled (12)" plane through (0, -16.9, 0) normal (0, 1, 0) x (1, 0, 0) in component "SERVICE HARDWARE | L6 upper cover"
  circle A0 centre (26, -8.1) radius 1.5
extrude "M3 shaft envelope; threads not modeled (1)'''''''''''" add sketch "M3 shaft envelope; threads not modeled (12)" along normal blind 30 separate body makes body 26 in component "SERVICE HARDWARE | L6 upper cover"
ref_plane "WorkPlane2" through (0, -18.7, 0) normal (0, 1, 0) x (0, 0, 1) in component "SERVICE HARDWARE | L6 upper cover"
sketch "Recessed socket head (12)" plane through (0, -18.7, 0) normal (0, 1, 0) x (1, 0, 0) in component "SERVICE HARDWARE | L6 upper cover"
  circle A0 centre (26, -8.1) radius 2.8
extrude "Recessed socket head (1)'''''''''''" add sketch "Recessed socket head (12)" along normal blind 1.8 bodies 26 in component "SERVICE HARDWARE | L6 upper cover"
component "CORE | CoreTub" placed x (1, 0, 0) y (0, 1, 0) z (0, 0, 1) at (0, 0, 0)
component "CORE | CoreLid" placed x (1, 0, 0) y (0, 1, 0) z (0, 0, 1) at (0, 0, 0)
component "CORE | ElectronicsCassette" placed x (1, 0, 0) y (0, 1, 0) z (0, 0, 1) at (0, 0, 0)
component "LEG | Centred proximal clevis" placed x (1, 0, 0) y (0, 1, 0) z (0, 0, 1) at (49, 0, 0)
component "LEG | Continuous centred upper enclosure" placed x (0.573576, 0, 0.819152) y (0, 1, 0) z (-0.819152, 0, 0.573576) at (94, 0, -12)
component "LEG | Full red front service panel" placed x (0.573576, 0, 0.819152) y (0, 1, 0) z (-0.819152, 0, 0.573576) at (94, 0, -12)
component "LEG | Centred tapered lower arm" placed x (0.309017, 0, -0.951057) y (0, 1, 0) z (0.951057, 0, 0.309017) at (123.826, 0, 30.5959)
component "FOOT | Centred soft toe boot" placed x (0.309017, 0, -0.951057) y (0, 1, 0) z (0.951057, 0, 0.309017) at (123.826, 0, 30.5959)
component "KEEP-OUT | YawReserve · actuator not selected" placed x (1, 0, 0) y (0, 1, 0) z (0, 0, 1) at (49, 0, 0)
component "KEEP-OUT | HipReserve · actuator not selected" placed x (0.573576, 0, 0.819152) y (0, 1, 0) z (-0.819152, 0, 0.573576) at (94, 0, -12)
component "KEEP-OUT | KneeReserve · actuator not selected" placed x (0.573576, 0, 0.819152) y (0, 1, 0) z (-0.819152, 0, 0.573576) at (94, 0, -12)
component "LEG | Centred proximal clevis" placed x (0.5, 0.866025, 0) y (-0.866025, 0.5, 0) z (0, 0, 1) at (24.5, 42.4352, 0)
component "LEG | Continuous centred upper enclosure" placed x (0.286788, 0.496732, 0.819152) y (-0.866025, 0.5, 0) z (-0.409576, -0.709406, 0.573576) at (47, 81.4064, -12)
component "LEG | Full red front service panel" placed x (0.286788, 0.496732, 0.819152) y (-0.866025, 0.5, 0) z (-0.409576, -0.709406, 0.573576) at (47, 81.4064, -12)
component "LEG | Centred tapered lower arm" placed x (0.154508, 0.267617, -0.951057) y (-0.866025, 0.5, 0) z (0.475528, 0.823639, 0.309017) at (61.913, 107.2364, 30.5959)
component "FOOT | Centred soft toe boot" placed x (0.154508, 0.267617, -0.951057) y (-0.866025, 0.5, 0) z (0.475528, 0.823639, 0.309017) at (61.913, 107.2364, 30.5959)
component "KEEP-OUT | YawReserve · actuator not selected" placed x (0.5, 0.866025, 0) y (-0.866025, 0.5, 0) z (0, 0, 1) at (24.5, 42.4352, 0)
component "KEEP-OUT | HipReserve · actuator not selected" placed x (0.286788, 0.496732, 0.819152) y (-0.866025, 0.5, 0) z (-0.409576, -0.709406, 0.573576) at (47, 81.4064, -12)
component "KEEP-OUT | KneeReserve · actuator not selected" placed x (0.286788, 0.496732, 0.819152) y (-0.866025, 0.5, 0) z (-0.409576, -0.709406, 0.573576) at (47, 81.4064, -12)
component "LEG | Centred proximal clevis" placed x (-0.5, 0.866025, 0) y (-0.866025, -0.5, 0) z (0, 0, 1) at (-24.5, 42.4352, 0)
component "LEG | Continuous centred upper enclosure" placed x (-0.286788, 0.496732, 0.819152) y (-0.866025, -0.5, 0) z (0.409576, -0.709406, 0.573576) at (-47, 81.4064, -12)
component "LEG | Full red front service panel" placed x (-0.286788, 0.496732, 0.819152) y (-0.866025, -0.5, 0) z (0.409576, -0.709406, 0.573576) at (-47, 81.4064, -12)
component "LEG | Centred tapered lower arm" placed x (-0.154508, 0.267617, -0.951057) y (-0.866025, -0.5, 0) z (-0.475528, 0.823639, 0.309017) at (-61.913, 107.2364, 30.5959)
component "FOOT | Centred soft toe boot" placed x (-0.154508, 0.267617, -0.951057) y (-0.866025, -0.5, 0) z (-0.475528, 0.823639, 0.309017) at (-61.913, 107.2364, 30.5959)
component "KEEP-OUT | YawReserve · actuator not selected" placed x (-0.5, 0.866025, 0) y (-0.866025, -0.5, 0) z (0, 0, 1) at (-24.5, 42.4352, 0)
component "KEEP-OUT | HipReserve · actuator not selected" placed x (-0.286788, 0.496732, 0.819152) y (-0.866025, -0.5, 0) z (0.409576, -0.709406, 0.573576) at (-47, 81.4064, -12)
component "KEEP-OUT | KneeReserve · actuator not selected" placed x (-0.286788, 0.496732, 0.819152) y (-0.866025, -0.5, 0) z (0.409576, -0.709406, 0.573576) at (-47, 81.4064, -12)
component "LEG | Centred proximal clevis" placed x (-1, 0, 0) y (0, -1, 0) z (0, 0, 1) at (-49, 0, 0)
component "LEG | Continuous centred upper enclosure" placed x (-0.573576, 0, 0.819152) y (0, -1, 0) z (0.819152, 0, 0.573576) at (-94, 0, -12)
component "LEG | Full red front service panel" placed x (-0.573576, 0, 0.819152) y (0, -1, 0) z (0.819152, 0, 0.573576) at (-94, 0, -12)
component "LEG | Centred tapered lower arm" placed x (-0.309017, 0, -0.951057) y (0, -1, 0) z (-0.951057, 0, 0.309017) at (-123.826, 0, 30.5959)
component "FOOT | Centred soft toe boot" placed x (-0.309017, 0, -0.951057) y (0, -1, 0) z (-0.951057, 0, 0.309017) at (-123.826, 0, 30.5959)
component "KEEP-OUT | YawReserve · actuator not selected" placed x (-1, 0, 0) y (0, -1, 0) z (0, 0, 1) at (-49, 0, 0)
component "KEEP-OUT | HipReserve · actuator not selected" placed x (-0.573576, 0, 0.819152) y (0, -1, 0) z (0.819152, 0, 0.573576) at (-94, 0, -12)
component "KEEP-OUT | KneeReserve · actuator not selected" placed x (-0.573576, 0, 0.819152) y (0, -1, 0) z (0.819152, 0, 0.573576) at (-94, 0, -12)
component "LEG | Centred proximal clevis" placed x (-0.5, -0.866025, 0) y (0.866025, -0.5, 0) z (0, 0, 1) at (-24.5, -42.4352, 0)